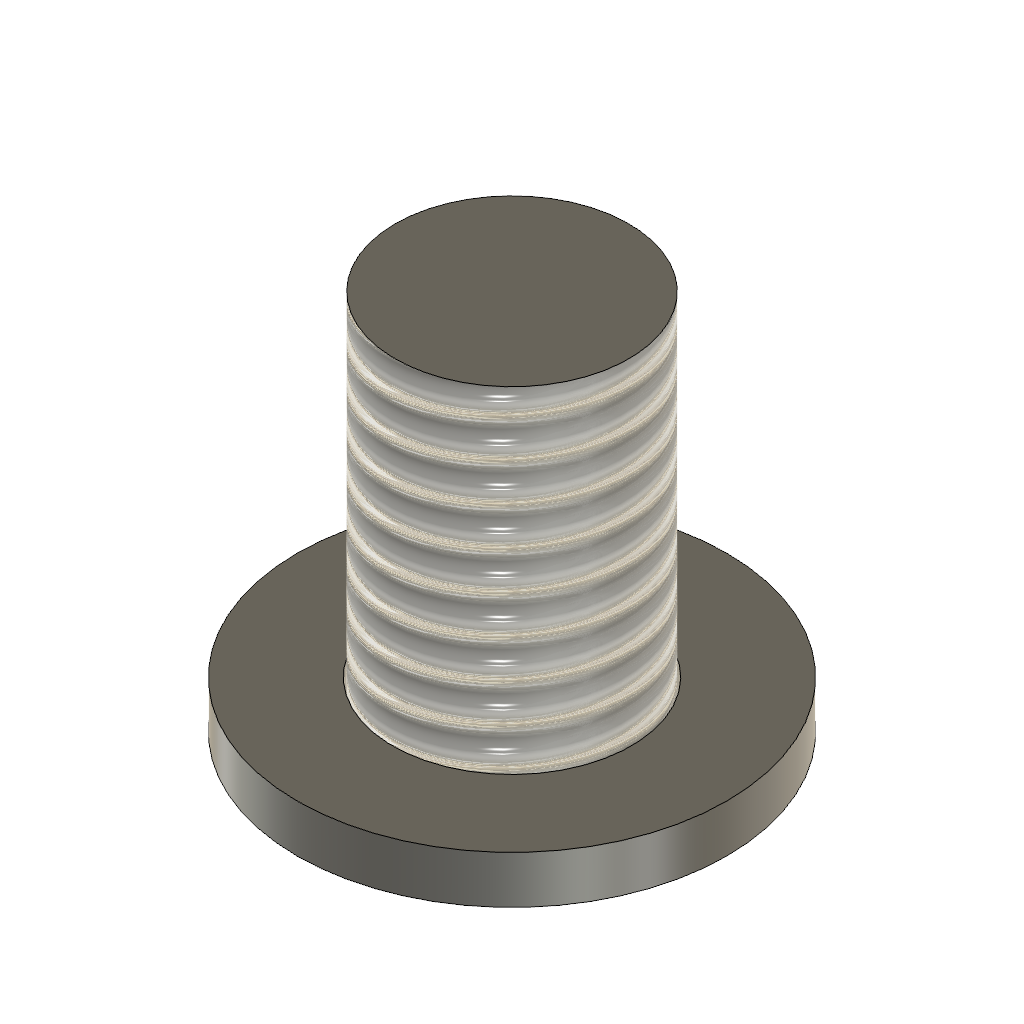
screws (Autodesk Fusion 360 design; units mm, degrees)
part number: 2026-10-03-18-51-59-198
Autodesk Fusion 360 part; units mm, degrees
sketch "Sketch1" plane through (0, 0, 0) normal (0, 0, 1) x (1, 0, 0)
  circle A0 centre (0, 0) radius 4.5
  circle A1 centre (0, 0) radius 2.5
  dimension "d1" = 9
  dimension "d2" = 5
  constraint coincident A0.centre A1.centre
  measures "d1" diameter of A0
  measures "d2" diameter of A1
extrude "Extrude1" add sketch "Sketch1" along normal blind 8 contours A1 makes body 1
extrude "Extrude2" add sketch "Sketch1" along normal blind 1 separate body makes body 2
thread "Thread1" "ISO Metric profile 5.0 M5x0.8 M5x0.8 6g" major diameter 4.901 minor diameter 3.9895 pitch 0.8 angle 60 resizes the face on face at (2.4969, -0.1246, 5.3333) on bodies 1
